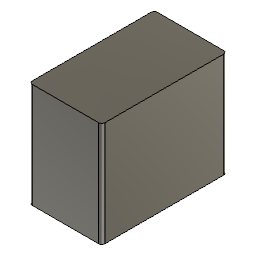
ryobiCharger (Autodesk Fusion 360 design; units mm, degrees)
part number: 2026-08-10-19-56-16-923
Autodesk Fusion 360 part; units mm, degrees
sketch "Sketch1" plane through (0, 0, 0) normal (0, 0, 1) x (1, 0, 0)
  line L0 (-28, 37) -> (62, 37)
  line L1 (62, 37) -> (62, 18)
  line L2 (62, 18) -> (-28, 18)
  line L3 (-28, 18) -> (-28, 37)
  dimension "d1" = 90
  dimension "d2" = 19
  constraint horizontal L0
  constraint vertical L1
  constraint horizontal L2
  constraint vertical L3
  measures "d1" distance of L0.start L0.end
  measures "d2" distance of L0.start L2.end
extrude "Extrude1" add sketch "Sketch1" along normal blind 6 makes body 1
sketch "Sketch2" plane through (0, 0, 6) normal (0, 0, 1) x (-1, 0, 0)
  line L0 (28, -37) -> (28, -18)
  line L1 (28, -18) -> (-62, -18)
  line L2 (-62, -18) -> (-62, -37)
  line L3 (-62, -37) -> (28, -37)
ref_plane "WorkPlane1" through (17, 27.5, 6) normal (0, 0, 1) x (-1, 0, 0)
sketch "Sketch3" plane through (0, 0, 6) normal (0, 0, 1) x (1, 0, 0)
  line L0 (17, 37) -> (17, 18)
  circle A0 centre (-8, 27.5) radius 8.9
  circle A1 centre (42, 27.5) radius 8.9
  circle A2 centre (-8, 27.5) radius 3.65
  circle A3 centre (42, 27.5) radius 3.65
  dimension "d13" = 17.8
  dimension "d14" = 17.8
  dimension "d15" = 7.3
  dimension "d16" = 7.3
  constraint vertical L0
  constraint concentric A0 A2
  constraint concentric A1 A3
  measures "d13" diameter of A0
  measures "d14" diameter of A1
  measures "d15" diameter of A2
  measures "d16" diameter of A3
extrude "Extrude2" cut sketch "Sketch3" against normal blind 7 contours A2 | A3 bodies 1
extrude "Extrude3" cut sketch "Sketch3" against normal blind 3 bodies 1
sketch "Sketch7" plane through (0, 0, 6) normal (0, 0, 1) x (-1, 0, 0)
  circle A0 centre (-42, -27.5) radius 8.9
  circle A1 centre (8, -27.5) radius 8.9
  line L0 (28, -18) -> (-62, -18)
  line L1 (-62, -18) -> (-62, -37)
  line L2 (-62, -37) -> (28, -37)
  line L3 (28, -37) -> (28, -18)
  line L4 (28, -18) -> (-62, -18)
  line L5 (-62, -18) -> (-62, -37)
  line L6 (28, -37) -> (28, -18)
  circle A2 centre (-42, -27.5) radius 8.9
  line L7 (-62, -37) -> (28, -37)
  circle A3 centre (8, -27.5) radius 8.9
  line L8 (8, -27.5) -> (8, 12.5)
  line L9 (8, 12.5) -> (-62, 12.5)
  line L10 (-62, 12.5) -> (-62, -18)
  line L11 (-62, -18) -> (8, -18)
  line L12 (8, -18) -> (8, 12.5)
  line L13 (8, 12.5) -> (28, 12.5)
  line L14 (28, 12.5) -> (28, -18)
  line L15 (28, -18) -> (8, -18)
  line L16 (8, -18) -> (8, 12.5)
  dimension "d42" = 40
  constraint coincident A1.centre A3.centre
  constraint perpendicular L0 L8
  constraint horizontal L9
  constraint vertical L10
  constraint horizontal L11
  constraint vertical L12
  constraint horizontal L13
  constraint vertical L14
  constraint horizontal L15
  constraint vertical L16
  measures "d42" distance of A1.centre L8.end
copy_body "CopyPasteBodies1" bodies 1 makes body 2
move_body "Move1" bodies 2 to x (1, 0, 0) y (0, 1, 0) z (0, 0, 1) at (0, 0, 0)
copy_body "CopyPasteBodies2" bodies 2 1 makes body 3 makes body 4
move_body "Move2" bodies 3 4 to x (1, 0, 0) y (0, 1, 0) z (0, 0, 1) at (0, 115, 0)
sketch "Sketch8" plane through (0, 0, 6) normal (0, 0, 1) x (-1, 0, 0)
  line L0 (-62, -37) -> (28, -37)
  line L1 (28, -37) -> (28, -133)
  line L2 (28, -133) -> (-62, -133)
  line L3 (-62, -133) -> (-62, -37)
  constraint horizontal L0
  constraint vertical L1
  constraint horizontal L2
  constraint vertical L3
extrude "Extrude7" add sketch "Sketch8" against normal blind 6 bodies 1 2 3 4
extrude "Extrude8" add sketch "Sketch7" against normal blind 6 contours L0 L4 L8 L12 L13 L14 L15 L16 | L0 L4 L8 L9 L10 L11 L12 L16 bodies 1
sketch "Sketch9" plane through (0, 0, 3) normal (0, 0, 1) x (-1, 0, 0)
  circle A0 centre (8, -142.5) radius 3.65
  circle A1 centre (8, -142.5) radius 8.9
  line L0 (8, -142.5) -> (8, -182.5)
  line L1 (8, -182.5) -> (28, -182.5)
  line L2 (28, -182.5) -> (28, -152)
  line L3 (28, -152) -> (8, -152)
  line L4 (8, -152) -> (8, -182.5)
  line L5 (8, -182.5) -> (-62, -182.5)
  line L6 (-62, -182.5) -> (-62, -152)
  line L7 (-62, -152) -> (8, -152)
  line L8 (8, -152) -> (8, -182.5)
  dimension "d45" = 40
  constraint coincident A0.centre A1.centre
  constraint vertical L0
  constraint horizontal L1
  constraint vertical L2
  constraint horizontal L3
  constraint vertical L4
  constraint horizontal L5
  constraint vertical L6
  constraint horizontal L7
  constraint vertical L8
  measures "d45" distance of A0.centre L0.end
extrude "Extrude9" add sketch "Sketch9" against normal blind 3 contours L0 L1 L2 L3 L4 L8 | L0 L4 L5 L6 L7 L8 bodies 1
extrude "Extrude10" add 1 faces at (32, 162.1667, 3) along direction (0, 0, 1) blind 3 on bodies 1 bodies 1
sketch "Sketch10" plane through (0, 0, 6) normal (0, 0, 1) x (-1, 0, 0)
  circle A0 centre (8, -142.5) radius 8.9
  circle A1 centre (-42, -142.5) radius 8.9
  circle A2 centre (-42, -27.5) radius 8.9
  circle A3 centre (8, -27.5) radius 8.9
  line L0 (-62, 12.5) -> (-62, -182.5)
  line L1 (-62, -182.5) -> (28, -182.5)
  line L2 (28, -182.5) -> (28, 12.5)
  line L3 (28, 12.5) -> (-62, 12.5)
  line L4 (28, -182.5) -> (-62, -182.5)
  line L5 (-62, -182.5) -> (-62, -162.5)
  line L6 (-62, -162.5) -> (28, -162.5)
  line L7 (28, -162.5) -> (28, -182.5)
  dimension "d50" = 20
  constraint horizontal L4
  constraint vertical L5
  constraint horizontal L6
  constraint vertical L7
  constraint coincident L1.end L2.start
  measures "d50" distance of L1.end L6.end
extrude "Extrude11" cut sketch "Sketch10" against normal blind 6 contours L0 L1 L2 L4 L5 L6 L7 bodies 1
sketch "Sketch11" plane through (0, 0, 6) normal (0, 0, 1) x (-1, 0, 0)
  line L0 (-62, -162.5) -> (28, -162.5)
  line L1 (28, -162.5) -> (28, 12.5)
  line L2 (28, 12.5) -> (-62, 12.5)
  line L3 (-62, 12.5) -> (-62, -162.5)
  circle A0 centre (8, -27.5) radius 8.9
  circle A1 centre (-42, -27.5) radius 8.9
  circle A2 centre (-42, -142.5) radius 8.9
  circle A3 centre (8, -142.5) radius 8.9
  line L4 (-62, 12.5) -> (28, 12.5)
  line L5 (28, 12.5) -> (28, -7.5)
  line L6 (28, -7.5) -> (-62, -7.5)
  line L7 (-62, -7.5) -> (-62, 12.5)
  dimension "d53" = 20
  constraint horizontal L4
  constraint vertical L5
  constraint horizontal L6
  constraint vertical L7
  constraint coincident L2.end L3.start
  measures "d53" distance of L2.end L6.end
extrude "Extrude12" cut sketch "Sketch11" against normal blind 6 contours L1 L2 L3 L4 L5 L6 L7 bodies 1
sketch "Sketch12" plane through (0, 0, 6) normal (0, 0, 1) x (-1, 0, 0)
  line L0 (28, -7.5) -> (-62, -7.5)
  line L1 (-62, -7.5) -> (-62, -162.5)
  line L2 (-62, -162.5) -> (28, -162.5)
  line L3 (28, -162.5) -> (28, -7.5)
  circle A0 centre (8, -27.5) radius 8.9
  circle A1 centre (-42, -27.5) radius 8.9
  circle A2 centre (-42, -142.5) radius 8.9
  circle A3 centre (8, -142.5) radius 8.9
  line L4 (-62, -162.5) -> (-58, -162.5)
  line L5 (-58, -162.5) -> (-58, -7.5)
  line L6 (-58, -7.5) -> (-62, -7.5)
  line L7 (-62, -7.5) -> (-62, -162.5)
  dimension "d56" = 4
  constraint horizontal L4
  constraint vertical L5
  constraint horizontal L6
  constraint vertical L7
  constraint coincident L1.end L2.start
  measures "d56" distance of L1.end L4.end
extrude "Extrude13" add sketch "Sketch12" along normal blind 124 contours L0 L1 L2 L4 L5 L6 L7 bodies 1
sketch "Sketch13" plane through (58, 0, 0) normal (-1, 0, 0) x (0, -1, 0)
  line L0 (-162.5, 6) -> (-7.5, 6)
  line L1 (-7.5, 6) -> (-7.5, 130)
  line L2 (-7.5, 130) -> (-162.5, 130)
  line L3 (-162.5, 130) -> (-162.5, 6)
  line L4 (-162.5, 130) -> (-7.5, 130)
  line L5 (-7.5, 130) -> (-7.5, 126)
  line L6 (-7.5, 126) -> (-162.5, 126)
  line L7 (-162.5, 126) -> (-162.5, 130)
  dimension "d59" = 4
  constraint horizontal L4
  constraint vertical L5
  constraint horizontal L6
  constraint vertical L7
  constraint coincident L2.end L3.start
  measures "d59" distance of L2.end L6.end
extrude "Extrude14" add sketch "Sketch13" along normal blind 86 contours L1 L2 L3 L4 L5 L6 L7 bodies 1
sketch "Sketch14" plane through (0, 7.5, 0) normal (0, -1, 0) x (1, 0, 0)
  line L0 (58, 6) -> (-28, 6)
  line L1 (-28, 6) -> (-28, 0)
  line L2 (-28, 0) -> (62, 0)
  line L3 (62, 0) -> (62, 130)
  line L4 (62, 130) -> (-28, 130)
  line L5 (-28, 130) -> (-28, 126)
  line L6 (-28, 126) -> (58, 126)
  line L7 (58, 126) -> (58, 6)
  line L8 (58, 126) -> (-28, 126)
  line L9 (-28, 126) -> (-28, 6)
  line L10 (-28, 6) -> (58, 6)
  line L11 (58, 6) -> (58, 126)
  constraint horizontal L8
  constraint vertical L9
  constraint horizontal L10
  constraint vertical L11
  constraint coincident L0.end L1.start
  constraint coincident L6.end L7.start
extrude "Extrude15" add sketch "Sketch14" against normal blind 4 contours L0 L6 L7 L8 L9 L10 L11 bodies 1
sketch "Sketch15" plane through (0, 162.5, 0) normal (0, 1, 0) x (-1, 0, 0)
  line L0 (-62, 130) -> (-62, 0)
  line L1 (-62, 0) -> (28, 0)
  line L2 (28, 0) -> (28, 6)
  line L3 (28, 6) -> (-58, 6)
  line L4 (-58, 6) -> (-58, 126)
  line L5 (-58, 126) -> (28, 126)
  line L6 (28, 126) -> (28, 130)
  line L7 (28, 130) -> (-62, 130)
  line L8 (-58, 126) -> (28, 126)
  line L9 (28, 126) -> (28, 6)
  line L10 (28, 6) -> (-58, 6)
  line L11 (-58, 6) -> (-58, 126)
  constraint horizontal L8
  constraint vertical L9
  constraint horizontal L10
  constraint vertical L11
  constraint coincident L2.end L3.start
  constraint coincident L4.end L5.start
extrude "Extrude16" add sketch "Sketch15" against normal blind 4 contours L3 L4 L5 L8 L9 L10 L11 bodies 1
fillet "Fillet3" radius 4 3 edges at (-28, 162.5, 65) (-28, 7.5, 65) (62, 7.5, 65) on bodies 1
fillet "Fillet4" radius 4 1 edges at (62, 162.5, 65) on bodies 1
